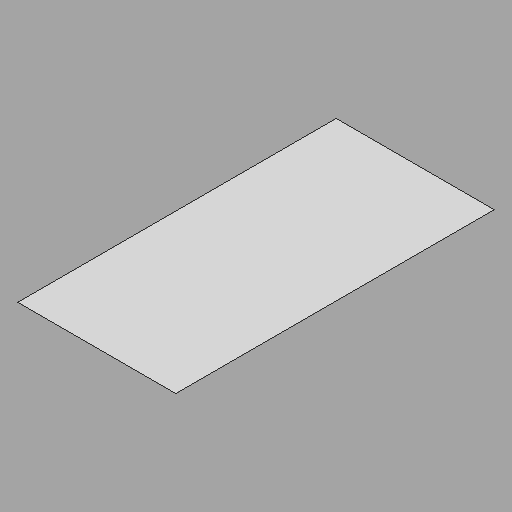
# Autodesk Inventor part: EVA
Saved by Autodesk Inventor 2026.2 (Build 302298000, 298)
## iProperties
Created: 2026-09-16
Part Number: EVA
Material: Polytetrafluoroethylene
Document SubType Name: Modeling
Designer: Jacob
Density: 2.02 g/cm^3
Appearance: Clear
EVA_Thickness: 0.500 mm
Author: Jacob
Autodesk Inventor part; units mm, degrees
ref_plane "YZ Plane" through (0, 0, 0) normal (1, 0, 0) x (0, 1, 0)
ref_plane "XZ Plane" through (0, 0, 0) normal (0, 1, 0) x (-1, 0, 0)
ref_plane "XY Plane" through (0, 0, 0) normal (0, 0, 1) x (1, 0, 0)
sketch "Sketch1" plane through (0, 0, 0) normal (0, 1, 0) x (-1, 0, 0)
  line L0 (-564, 1136.5) -> (564, 1136.5)
  line L1 (564, 1136.5) -> (564, -1136.5)
  line L2 (564, -1136.5) -> (-564, -1136.5)
  line L3 (-564, -1136.5) -> (-564, 1136.5)
  line L4 (-564, 1136.5) -> (564, -1136.5) construction
  line L5 (564, 1136.5) -> (-564, -1136.5) construction
  dimension "d0" = 1128
  dimension "d1" = 2273
  constraints: 12 end point, 2 parallel, 1 horizontal, 1 perpendicular
  measures "d0" distance of L1.end L2.end
  measures "d1" distance of L0.end L1.end
extrude "Extrusion2" add sketch "Sketch1" along normal blind 0.5
equation "\"d12\" = EVA_Thickness"
equation "\"EVA_Thickness\" = 0.5"
body "Solid2"
